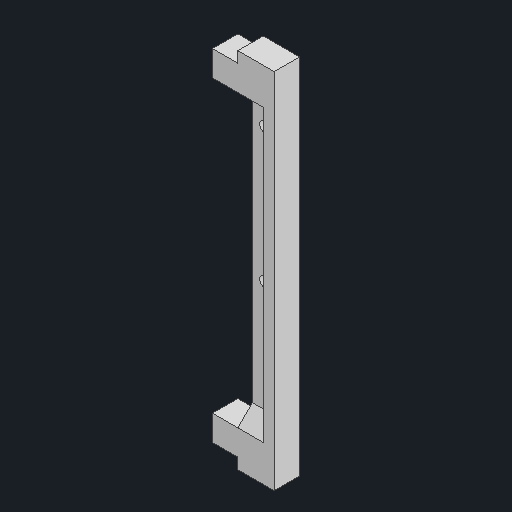
# Autodesk Inventor part: Moter_Fix_Side
Saved by Autodesk Inventor 2027.1 (Build 311270010, 270A)
## iProperties
Created: 2026-11-11
Part Number: Moter_Fix_Side
Material: 一般
Document SubType Name: Modeling
Designer: takuya
Density: 1 g/cm^3
Appearance: 既定
Author: takuya
Autodesk Inventor part; units mm, degrees
ref_plane "YZ Plane" through (0, 0, 0) normal (1, 0, 0) x (0, 1, 0)
ref_plane "XZ Plane" through (0, 0, 0) normal (0, 1, 0) x (-1, 0, 0)
ref_plane "XY Plane" through (0, 0, 0) normal (0, 0, 1) x (1, 0, 0)
sketch "スケッチ1" plane through (0, 0, 0) normal (0, 0, 1) x (1, 0, 0)
  line L0 (-40, 0) -> (0, 0) projected
  line L1 (-40, 0) -> (-40, -3) projected
  line L2 (0, -3) -> (-40, -3) projected
  line L3 (0, 0) -> (0, -3) projected
  line L4 (0, -97) -> (-40, -97) projected
  line L5 (-40, -97) -> (-40, -100) projected
  line L6 (0, -100) -> (-40, -100) projected
  line L7 (0, -97) -> (0, -100) projected
  line L8 (0, -100) -> (7, -100)
  line L9 (7, -100) -> (7, 0)
  line L10 (7, 0) -> (0, 0)
  line L11 (0, 0) -> (0, -100)
  line L12 (0, -97) -> (-7, -97)
  line L13 (-7, -97) -> (-7, -90)
  line L14 (-7, -90) -> (0, -90)
  line L15 (0, -90) -> (0, -97)
  line L16 (0, -71) -> (-40, -71)
  line L17 (0, -71) -> (-7, -71)
  line L18 (-7, -71) -> (-7, -64)
  line L19 (-7, -64) -> (0, -64)
  line L20 (0, -64) -> (0, -71)
  line L21 (0, -3) -> (-7, -3)
  line L22 (-7, -3) -> (-7, -10)
  line L23 (-7, -10) -> (0, -10)
  line L24 (0, -10) -> (0, -3)
  dimension "d0" = 7
  dimension "d1" = 7
  dimension "d2" = 7
  dimension "d3" = 7
  dimension "d4" = 7
  dimension "d5" = 7
  dimension "d6" = 7
  constraints: 34 end point, 7 parallel, 3 horizontal, 3 perpendicular
  measures "d0" distance of L10.end L9.end
  measures "d1" distance of L13.end L14.end
  measures "d2" distance of L12.end L13.end
  measures "d3" distance of L18.end L19.end
  measures "d4" distance of L17.end L18.end
  measures "d5" distance of L23.end L22.end
  measures "d6" distance of L22.end L21.end
extrude "押し出し1" add sketch "スケッチ1" against normal blind 7 contours L10 L9 L8 L7 L11 L3 | L11 L23 L22 L2 | L4 L13 L14 L11
sketch "スケッチ2" plane through (0, 0, 0) normal (0, 0, 1) x (1, 0, 0)
  line L0 (0, 0) -> (0, -3) projected
  line L1 (0, -3) -> (-7, -3) projected
  line L2 (-7, -3) -> (-7, -10) projected
  line L3 (-7, -10) -> (0, -10) projected
  line L4 (0, -10) -> (0, -90) projected
  line L5 (0, -90) -> (-7, -90) projected
  line L6 (-7, -90) -> (-7, -97) projected
  line L7 (-7, -97) -> (0, -97) projected
  line L8 (0, -97) -> (0, -100) projected
  line L9 (0, -100) -> (7, -100) projected
  line L10 (7, -100) -> (7, 0) projected
  line L11 (7, 0) -> (0, 0) projected
  line L12 (3.5, -57) -> (3.5, -17) construction
  line L13 (5, -55.5) -> (5, -18.5)
  line L14 (2, -18.5) -> (2, -55.5)
  arc A0 (2, -55.5) -> (5, -55.5) centre (3.5, -55.5) ccw
  arc A1 (5, -18.5) -> (2, -18.5) centre (3.5, -18.5) ccw
  line L15 (0, -10) -> (7, -10)
  line L16 (7, -10) -> (7, -17)
  line L17 (7, -17) -> (0, -17)
  line L18 (0, -17) -> (0, -10)
  point P0 (3.5, -37)
  dimension "d9" = 3
  dimension "d17" = 40
  dimension "d18" = 7
  constraints: 16 end point, 6 point on circle, 5 tangent, 4 parallel, 3 point on line, 2 centre point, 1 horizontal, 1 midpoint, 1 perpendicular
  measures "d9" diameter of A1
  measures "d17" distance of L12.start L12.end
  measures "d18" distance of L15.end L16.end
extrude "押し出し2" cut sketch "スケッチ2" against normal blind 7 contours A1 L13 A0 L14
sketch "スケッチ3" plane through (0, 0, 0) normal (0, 0, 1) x (1, 0, 0)
  line L0 (2, -55.5) -> (2, -18.5) projected
  arc A0 (5, -18.5) -> (2, -18.5) centre (3.5, -18.5) ccw projected
  line L1 (5, -18.5) -> (5, -55.5) projected
  arc A1 (2, -55.5) -> (5, -55.5) centre (3.5, -55.5) ccw projected
  line L2 (0, 0) -> (0, -3) projected
  line L3 (0, -3) -> (-7, -3) projected
  line L4 (-7, -3) -> (-7, -10) projected
  line L5 (-7, -10) -> (0, -10) projected
  line L6 (0, -10) -> (0, -90) projected
  line L7 (0, -90) -> (-7, -90) projected
  line L8 (-7, -90) -> (-7, -97) projected
  line L9 (-7, -97) -> (0, -97) projected
  line L10 (0, -97) -> (0, -100) projected
  line L11 (0, -100) -> (7, -100) projected
  line L12 (7, -100) -> (7, 0) projected
  line L13 (7, 0) -> (0, 0) projected
  line L14 (0, -90) -> (8.1526, -90)
  line L15 (8.1526, -90) -> (8.1526, -10)
  line L16 (8.1526, -10) -> (0, -10)
  line L17 (0, -10) -> (0, -90)
  point P0 (7, -10)
  point P1 (7, -90)
  constraints: 8 end point, 2 parallel, 1 horizontal, 1 perpendicular
extrude "押し出し3" cut sketch "スケッチ3" against normal blind 4 contours L12 L14 L6 L16
chamfer "面取り1" distance 4 angle 45 2 edges at (3.5, -10, -4) (3.5, -90, -4)
sketch "スケッチ4" plane through (7, -100, -7) normal (1, 0, 0) x (0, 0, -1)
  line L0 (0, 97) -> (0, 100) projected
  line L1 (-7, 0) -> (0, 0) projected
  line L2 (0, 100) -> (-7, 100)
  line L3 (-7, 100) -> (-7, 0)
  line L4 (-7, 0) -> (0, 0)
  line L5 (0, 0) -> (0, 100)
  constraints: 8 end point, 2 parallel, 1 horizontal, 1 perpendicular
extrude "押し出し4" add sketch "スケッチ4" along normal blind 3
sketch "スケッチ5" plane through (0, 0, -4) normal (0, 0, 1) x (1, 0, 0)
  line L0 (7, -86) -> (0, -86) projected
  line L1 (7, -14) -> (7, -86) projected
  line L2 (0, -14) -> (7, -14) projected
  line L3 (0, -86) -> (0, -14) projected
  line L4 (5, -55.5) -> (5, -18.5) projected
  arc A0 (2, -55.5) -> (5, -55.5) centre (3.5, -55.5) ccw projected
  line L5 (2, -18.5) -> (2, -55.5) projected
  arc A1 (5, -18.5) -> (2, -18.5) centre (3.5, -18.5) ccw projected
  circle A2 centre (3.5, -55.5) radius 1.5
  circle A3 centre (3.5, -18.5) radius 1.5
  point P0 (0, 0)
  point P1 (5, -55.5)
  point P2 (2, -55.5)
  constraints: 2 centre point, 2 coincident, 2 tangent
extrude "押し出し5" add sketch "スケッチ5" against normal up to surface (3 mm away) contours A2 L5 A3 L4
